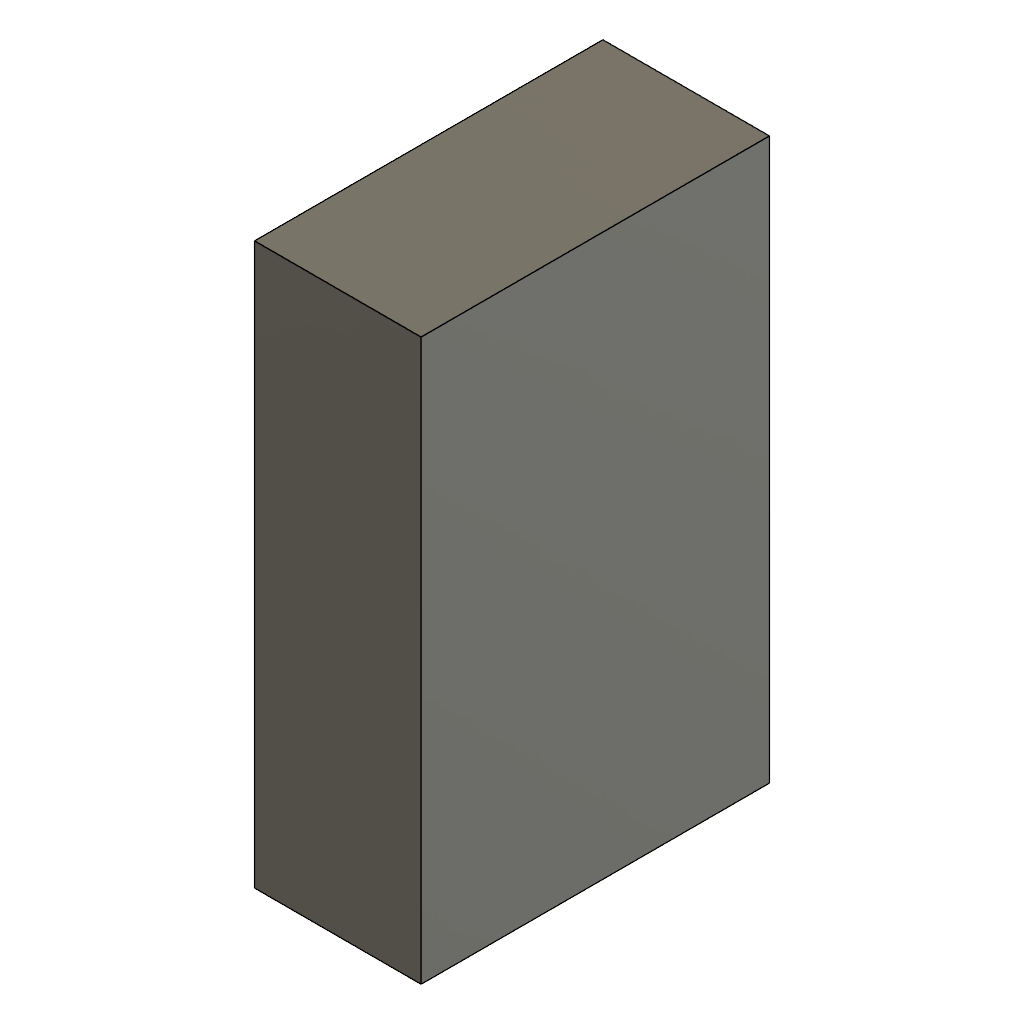
forward-yz (Autodesk Fusion 360 design; units mm, degrees)
part number: 2026-11-22-21-15-17-292
Autodesk Fusion 360 part; units mm, degrees
sketch "RectangleSketch" plane through (0, 0, 0) normal (1, 0, 0) x (0, 0, -1)
  line L0 (0, 0) -> (0, 37)
  line L1 (0, 37) -> (-23, 37)
  line L2 (-23, 37) -> (-23, 0)
  line L3 (-23, 0) -> (0, 0)
  dimension "width_mm" = 37
  dimension "height_mm" = 23
  constraint vertical L0
  constraint horizontal L1
  constraint vertical L2
  constraint horizontal L3
  constraint coincident L0.start L3.end
  measures "width_mm" vertical distance of L0.start L0.end
  measures "height_mm" horizontal distance of L0.start L2.end
extrude "BlindBoss" add sketch "RectangleSketch" along normal blind 11
equation "depth_mm = 11 mm"
